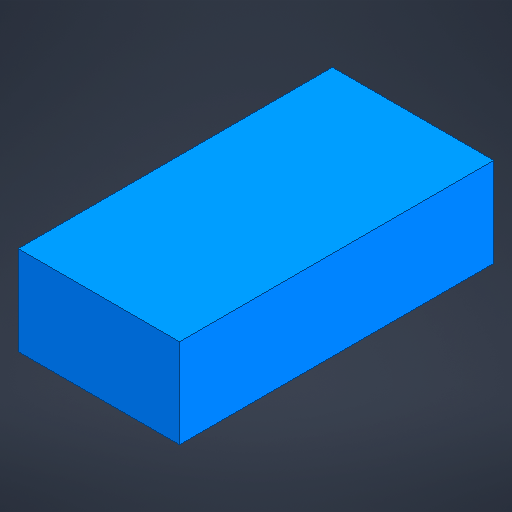
# Autodesk Inventor part: battery_control
Saved by Autodesk Inventor 2026.2 (Build 302298010, 298A)
## iProperties
Created: 2026-10-26
Part Number: battery_control
Material: Générique
Document SubType Name: Modeling
Designer: User
Density: 1 g/cm^3
Appearance: Par défaut
Author: User
Autodesk Inventor part; units mm, degrees
ref_plane "YZ Plane" through (0, 0, 0) normal (1, 0, 0) x (0, 1, 0)
ref_plane "XZ Plane" through (0, 0, 0) normal (0, 1, 0) x (-1, 0, 0)
ref_plane "XY Plane" through (0, 0, 0) normal (0, 0, 1) x (1, 0, 0)
sketch "Esquisse1" plane through (0, 0, 0) normal (0, 0, 1) x (1, 0, 0)
  line L0 (-30.95, 13.38) -> (7.05, 13.38)
  line L1 (7.05, 13.38) -> (7.05, -7.62)
  line L2 (7.05, -7.62) -> (-30.95, -7.62)
  line L3 (-30.95, -7.62) -> (-30.95, 13.38)
  point P0 (0, 0)
  dimension "d0" = 21
  dimension "d1" = 38
  constraints: 8 end point, 2 parallel, 1 horizontal, 1 perpendicular
  measures "d0" distance of L0.end L1.end
  measures "d1" distance of L0.start L0.end
extrude "Extrusion1" add sketch "Esquisse1" along normal blind 74
